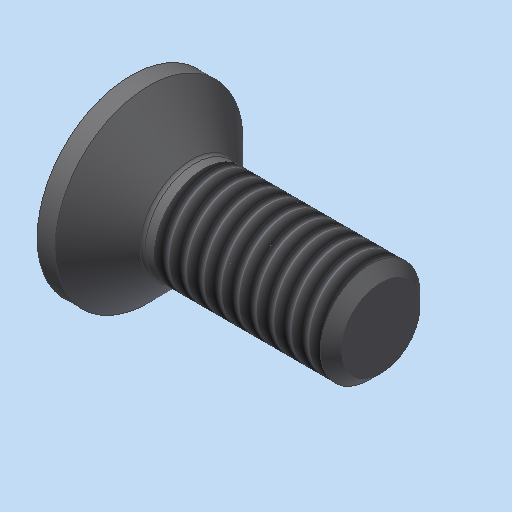
# Autodesk Inventor part: Senkschraube_ISO_10642___M4x10
Saved by Autodesk Inventor 2023.3 (Build 273359000, 359)
## iProperties
Shininess: 64.0
Length Units: 11269
Angle Units: 11279
Time Units: 11290
Mass Units: 11283
Length Display Precision: 3
Angle Display Precision: 2
Compacted: True
Part Number: Senkschraube_ISO_10642___M4x10
Document SubType Name: Modeling
Created: 2004-03-30
Material: xStahl_AnP_Dummymaterial
Description: =<RBPARTNOTITLE2>
Vendor: NORM8
Designer: S.Riedelsheimer
Manufacturer: Standard
Standards Organization: Custom
Density: 7.85 g/cm^3
Appearance: Stahl - normal AnP
Mass: 1.29245 g
Surface Area: 2.2295 cm^2
Volume: 0.164644 cm^3
DOC_ID: 5 F45 Senkschraube_ISO_10642___M4x10
GAIN_REFID: 20__Senkschraube_ISO_10642___M4x10:910A0
Control State: 0
Master: False
Checked Out: False
CNS_NB: Senkschraube ISO 10642 - M4x10
CNS_NN: ISO 10642
CNS_NT: Senkschrauben mit Innensechskant
CNS_NBSYN: Senkschraube $NENN.
CNS_LINA: Senkschraube ISO 10642 - M4x10
CNS_D: 4.000
CNS_D3: 3.141
CNS_P: 0.700
CNS_L: 10.000
CNS_S: 2.500
CNS_DK: 7.530
CNS_K: 2.480
CNS_T: 1.500
CNS_R: 0.200
CNS_LS: 0.000
CNS_LG: 0.000
CNS_NENN: ISO 10642 - M4x10
CNS_YW: 1.571
CNS_YC: 0.715
CNS_KT: DUMMY
PSOL_IDENT_0: {C:\partsolutions8\data\23d-libs\bosch_bamberg\schrauben\senkschrauben\iso_10642.prj},167 {M=Nenngew
PSOL_IDENT_1: inde},{VTYP=3D},{NB=Senkschraube ISO 10642 - M4x10},{NN=ISO 10642},{DATE=26.11.2003},{GEOMDATE=26.11
PSOL_IDENT_2: .2003},{VERSION=v1},{LINEID=90},{LINESUBID=-1},{WBVAR=}  {NB=Senkschraube ISO 10642 - M4x10},{LINA=S
PSOL_IDENT_3: enkschraube ISO 10642 - M4x10},{KT=DUMMY},{IDNR=},{D=4.000},{D3=3.141},{P=0.700},{L=10.000},{S=2.500
PSOL_IDENT_4: },{DK=7.530},{K=2.480},{T=1.500},{R=0.200},{LS=0.000},{LG=0.000},{NENN=ISO 10642 - M4x10},{YW=1.5707
PSOL_IDENT_5: 9},{YC=0.714989}
DEF_STKID: T18914
Bezeichnung1: Senkschraube ISO 10642 - M4x10
Bezeichnung2: Senkschrauben mit Innensechskant
RBPARTNOTITLE2: Senkschrauben mit Innensechskant
RBPARTMADEOF: ISO 10642 - M4x10
RBPARTNOTITLE1: Hexagon socket countersunk head screws
RBDRAWINGMISSINGSPEC: --
AnP_Kategorie: 4
Density: 0.0
Volumn: 0.0
Area: 0.0
PropertySet Name: Model Information
Title: Senkschraube ISO 10642 - M4x10
Author: S.Riedelsheimer
Keywords: =<RBPARTMADEOF>
Comments: =<RBSURFACE2>
Revision Number: 01
Autodesk Inventor part; units mm, degrees
sketch "Sketch_1" plane through (0, 0, 0) normal (0, 0, 1) x (1, 0, 0)
  line L0 (0.3868, 0) -> (10, 0)
  line L1 (10, 0) -> (10, -1.5705)
  line L2 (10, -1.5705) -> (9.5705, -2)
  line L3 (9.5705, -2) -> (2.5628, -2)
  arc A0 (2.5628, -2) -> (2.4214, -2.0586) centre (2.5628, -2.2) ccw
  line L4 (2.4214, -2.0586) -> (0.715, -3.765)
  line L5 (0.715, -3.765) -> (0, -3.765)
  line L6 (0, -3.765) -> (0, -1.4434)
  line L7 (0, -1.4434) -> (0.3868, 0)
  line L8 (0.3868, 0) -> (10, 0)
  constraints: 18 end point, 2 point on circle, 1 centre point
revolve "Drehung1" add sketch "Sketch_1" angle 360 about axis through (0.3868, 0, 0) along (1, 0, 0)
thread "Gewinde1" size "M4x0.7" class "6g" standard "ANSI Metric M Profile" length 6.661
sketch "Sketch_3" plane through (0, 0, 0) normal (1, 0, 0) x (0, 1, 0)
  line L0 (0, 1.4434) -> (-1.25, 0.7217)
  line L1 (-1.25, 0.7217) -> (-1.25, -0.7217)
  line L2 (-1.25, -0.7217) -> (0, -1.4434)
  line L3 (0, -1.4434) -> (1.25, -0.7217)
  line L4 (1.25, -0.7217) -> (1.25, 0.7217)
  line L5 (1.25, 0.7217) -> (0, 1.4434)
  constraints: 12 end point
extrude "Extrusion1" cut sketch "Sketch_3" along normal blind 1.5
ref_plane "IP1_XY" through (0, 0, 0) normal (1, 0, 0) x (0, 0, -1)
ref_plane "IP1_YZ" through (0, 0, 0) normal (0, 0, -1) x (0, 1, 0)
ref_plane "IP2_XY" through (10, 0, 0) normal (1, 0, 0) x (0, 0, -1)
ref_plane "IP2_YZ" through (10, 0, 0) normal (0, 0, -1) x (0, 1, 0)
